Autodesk Fusion 360 part; units mm, degrees
(part 6 of 8)
sketch "Fixed metal roller pin 4 | profile" plane through (0, 0, -17) normal (0, 0, 1) x (1, 0, 0) in component "11:1 twin-disc shoulder | original geometry"
  circle A0 centre (0, 40) radius 1.5
extrude "Fixed metal roller pin 4" add sketch "Fixed metal roller pin 4 | profile" along normal blind 34 separate body makes body 239 in component "11:1 twin-disc shoulder | original geometry"
ref_plane "WorkPlane36" through (0, 0, -6) normal (0, 0, 1) x (1, 0, 0) in component "11:1 twin-disc shoulder | original geometry"
sketch "623ZZ outer race | profile (6)" plane through (0, 0, -6) normal (0, 0, 1) x (1, 0, 0) in component "11:1 twin-disc shoulder | original geometry"
  circle A0 centre (0, 40) radius 5
  circle A1 centre (0, 40) radius 4
extrude "623ZZ outer race (6)" add sketch "623ZZ outer race | profile (6)" along normal blind 4 separate body makes body 240 in component "11:1 twin-disc shoulder | original geometry"
ref_plane "WorkPlane37" through (0, 0, -6) normal (0, 0, 1) x (1, 0, 0) in component "11:1 twin-disc shoulder | original geometry"
sketch "623ZZ inner race | profile (6)" plane through (0, 0, -6) normal (0, 0, 1) x (1, 0, 0) in component "11:1 twin-disc shoulder | original geometry"
  circle A0 centre (0, 40) radius 2.5
  circle A1 centre (0, 40) radius 1.5
extrude "623ZZ inner race (6)" add sketch "623ZZ inner race | profile (6)" along normal blind 4 separate body makes body 241 in component "11:1 twin-disc shoulder | original geometry"
ref_plane "WorkPlane38" through (0, 0, -5.85) normal (0, 0, 1) x (1, 0, 0) in component "11:1 twin-disc shoulder | original geometry"
sketch "623ZZ shield | profile (6)" plane through (0, 0, -5.85) normal (0, 0, 1) x (1, 0, 0) in component "11:1 twin-disc shoulder | original geometry"
  circle A0 centre (0, 40) radius 4
  circle A1 centre (0, 40) radius 2.5
extrude "623ZZ shield (6)" add sketch "623ZZ shield | profile (6)" along normal blind 3.7 separate body makes body 242 in component "11:1 twin-disc shoulder | original geometry"
ref_plane "WorkPlane39" through (0, 0, 2) normal (0, 0, 1) x (1, 0, 0) in component "11:1 twin-disc shoulder | original geometry"
sketch "623ZZ outer race | profile (7)" plane through (0, 0, 2) normal (0, 0, 1) x (1, 0, 0) in component "11:1 twin-disc shoulder | original geometry"
  circle A0 centre (0, 40) radius 5
  circle A1 centre (0, 40) radius 4
extrude "623ZZ outer race (7)" add sketch "623ZZ outer race | profile (7)" along normal blind 4 separate body makes body 243 in component "11:1 twin-disc shoulder | original geometry"
ref_plane "WorkPlane40" through (0, 0, 2) normal (0, 0, 1) x (1, 0, 0) in component "11:1 twin-disc shoulder | original geometry"
sketch "623ZZ inner race | profile (7)" plane through (0, 0, 2) normal (0, 0, 1) x (1, 0, 0) in component "11:1 twin-disc shoulder | original geometry"
  circle A0 centre (0, 40) radius 2.5
  circle A1 centre (0, 40) radius 1.5
extrude "623ZZ inner race (7)" add sketch "623ZZ inner race | profile (7)" along normal blind 4 separate body makes body 244 in component "11:1 twin-disc shoulder | original geometry"
ref_plane "WorkPlane41" through (0, 0, 2.15) normal (0, 0, 1) x (1, 0, 0) in component "11:1 twin-disc shoulder | original geometry"
sketch "623ZZ shield | profile (7)" plane through (0, 0, 2.15) normal (0, 0, 1) x (1, 0, 0) in component "11:1 twin-disc shoulder | original geometry"
  circle A0 centre (0, 40) radius 4
  circle A1 centre (0, 40) radius 2.5
extrude "623ZZ shield (7)" add sketch "623ZZ shield | profile (7)" along normal blind 3.7 separate body makes body 245 in component "11:1 twin-disc shoulder | original geometry"
ref_plane "WorkPlane42" through (0, 0, -17) normal (0, 0, 1) x (1, 0, 0) in component "11:1 twin-disc shoulder | original geometry"
sketch "Fixed metal roller pin 5 | profile" plane through (0, 0, -17) normal (0, 0, 1) x (1, 0, 0) in component "11:1 twin-disc shoulder | original geometry"
  circle A0 centre (-20, 34.641) radius 1.5
extrude "Fixed metal roller pin 5" add sketch "Fixed metal roller pin 5 | profile" along normal blind 34 separate body makes body 246 in component "11:1 twin-disc shoulder | original geometry"
ref_plane "WorkPlane43" through (0, 0, -6) normal (0, 0, 1) x (1, 0, 0) in component "11:1 twin-disc shoulder | original geometry"
sketch "623ZZ outer race | profile (8)" plane through (0, 0, -6) normal (0, 0, 1) x (1, 0, 0) in component "11:1 twin-disc shoulder | original geometry"
  circle A0 centre (-20, 34.641) radius 5
  circle A1 centre (-20, 34.641) radius 4
extrude "623ZZ outer race (8)" add sketch "623ZZ outer race | profile (8)" along normal blind 4 separate body makes body 247 in component "11:1 twin-disc shoulder | original geometry"
ref_plane "WorkPlane44" through (0, 0, -6) normal (0, 0, 1) x (1, 0, 0) in component "11:1 twin-disc shoulder | original geometry"
sketch "623ZZ inner race | profile (8)" plane through (0, 0, -6) normal (0, 0, 1) x (1, 0, 0) in component "11:1 twin-disc shoulder | original geometry"
  circle A0 centre (-20, 34.641) radius 2.5
  circle A1 centre (-20, 34.641) radius 1.5
extrude "623ZZ inner race (8)" add sketch "623ZZ inner race | profile (8)" along normal blind 4 separate body makes body 248 in component "11:1 twin-disc shoulder | original geometry"
ref_plane "WorkPlane45" through (0, 0, -5.85) normal (0, 0, 1) x (1, 0, 0) in component "11:1 twin-disc shoulder | original geometry"
sketch "623ZZ shield | profile (8)" plane through (0, 0, -5.85) normal (0, 0, 1) x (1, 0, 0) in component "11:1 twin-disc shoulder | original geometry"
  circle A0 centre (-20, 34.641) radius 4
  circle A1 centre (-20, 34.641) radius 2.5
extrude "623ZZ shield (8)" add sketch "623ZZ shield | profile (8)" along normal blind 3.7 separate body makes body 249 in component "11:1 twin-disc shoulder | original geometry"
ref_plane "WorkPlane46" through (0, 0, 2) normal (0, 0, 1) x (1, 0, 0) in component "11:1 twin-disc shoulder | original geometry"
sketch "623ZZ outer race | profile (9)" plane through (0, 0, 2) normal (0, 0, 1) x (1, 0, 0) in component "11:1 twin-disc shoulder | original geometry"
  circle A0 centre (-20, 34.641) radius 5
  circle A1 centre (-20, 34.641) radius 4
extrude "623ZZ outer race (9)" add sketch "623ZZ outer race | profile (9)" along normal blind 4 separate body makes body 250 in component "11:1 twin-disc shoulder | original geometry"
ref_plane "WorkPlane47" through (0, 0, 2) normal (0, 0, 1) x (1, 0, 0) in component "11:1 twin-disc shoulder | original geometry"
sketch "623ZZ inner race | profile (9)" plane through (0, 0, 2) normal (0, 0, 1) x (1, 0, 0) in component "11:1 twin-disc shoulder | original geometry"
  circle A0 centre (-20, 34.641) radius 2.5
  circle A1 centre (-20, 34.641) radius 1.5
extrude "623ZZ inner race (9)" add sketch "623ZZ inner race | profile (9)" along normal blind 4 separate body makes body 251 in component "11:1 twin-disc shoulder | original geometry"
ref_plane "WorkPlane48" through (0, 0, 2.15) normal (0, 0, 1) x (1, 0, 0) in component "11:1 twin-disc shoulder | original geometry"
sketch "623ZZ shield | profile (9)" plane through (0, 0, 2.15) normal (0, 0, 1) x (1, 0, 0) in component "11:1 twin-disc shoulder | original geometry"
  circle A0 centre (-20, 34.641) radius 4
  circle A1 centre (-20, 34.641) radius 2.5
extrude "623ZZ shield (9)" add sketch "623ZZ shield | profile (9)" along normal blind 3.7 separate body makes body 252 in component "11:1 twin-disc shoulder | original geometry"
ref_plane "WorkPlane49" through (0, 0, -17) normal (0, 0, 1) x (1, 0, 0) in component "11:1 twin-disc shoulder | original geometry"
sketch "Fixed metal roller pin 6 | profile" plane through (0, 0, -17) normal (0, 0, 1) x (1, 0, 0) in component "11:1 twin-disc shoulder | original geometry"
  circle A0 centre (-34.641, 20) radius 1.5
extrude "Fixed metal roller pin 6" add sketch "Fixed metal roller pin 6 | profile" along normal blind 34 separate body makes body 253 in component "11:1 twin-disc shoulder | original geometry"
ref_plane "WorkPlane50" through (0, 0, -6) normal (0, 0, 1) x (1, 0, 0) in component "11:1 twin-disc shoulder | original geometry"
sketch "623ZZ outer race | profile (10)" plane through (0, 0, -6) normal (0, 0, 1) x (1, 0, 0) in component "11:1 twin-disc shoulder | original geometry"
  circle A0 centre (-34.641, 20) radius 5
  circle A1 centre (-34.641, 20) radius 4
extrude "623ZZ outer race (10)" add sketch "623ZZ outer race | profile (10)" along normal blind 4 separate body makes body 254 in component "11:1 twin-disc shoulder | original geometry"
ref_plane "WorkPlane51" through (0, 0, -6) normal (0, 0, 1) x (1, 0, 0) in component "11:1 twin-disc shoulder | original geometry"
sketch "623ZZ inner race | profile (10)" plane through (0, 0, -6) normal (0, 0, 1) x (1, 0, 0) in component "11:1 twin-disc shoulder | original geometry"
  circle A0 centre (-34.641, 20) radius 2.5
  circle A1 centre (-34.641, 20) radius 1.5
extrude "623ZZ inner race (10)" add sketch "623ZZ inner race | profile (10)" along normal blind 4 separate body makes body 255 in component "11:1 twin-disc shoulder | original geometry"
ref_plane "WorkPlane52" through (0, 0, -5.85) normal (0, 0, 1) x (1, 0, 0) in component "11:1 twin-disc shoulder | original geometry"
sketch "623ZZ shield | profile (10)" plane through (0, 0, -5.85) normal (0, 0, 1) x (1, 0, 0) in component "11:1 twin-disc shoulder | original geometry"
  circle A0 centre (-34.641, 20) radius 4
  circle A1 centre (-34.641, 20) radius 2.5
extrude "623ZZ shield (10)" add sketch "623ZZ shield | profile (10)" along normal blind 3.7 separate body makes body 256 in component "11:1 twin-disc shoulder | original geometry"
ref_plane "WorkPlane53" through (0, 0, 2) normal (0, 0, 1) x (1, 0, 0) in component "11:1 twin-disc shoulder | original geometry"
sketch "623ZZ outer race | profile (11)" plane through (0, 0, 2) normal (0, 0, 1) x (1, 0, 0) in component "11:1 twin-disc shoulder | original geometry"
  circle A0 centre (-34.641, 20) radius 5
  circle A1 centre (-34.641, 20) radius 4
extrude "623ZZ outer race (11)" add sketch "623ZZ outer race | profile (11)" along normal blind 4 separate body makes body 257 in component "11:1 twin-disc shoulder | original geometry"
ref_plane "WorkPlane54" through (0, 0, 2) normal (0, 0, 1) x (1, 0, 0) in component "11:1 twin-disc shoulder | original geometry"
sketch "623ZZ inner race | profile (11)" plane through (0, 0, 2) normal (0, 0, 1) x (1, 0, 0) in component "11:1 twin-disc shoulder | original geometry"
  circle A0 centre (-34.641, 20) radius 2.5
  circle A1 centre (-34.641, 20) radius 1.5
extrude "623ZZ inner race (11)" add sketch "623ZZ inner race | profile (11)" along normal blind 4 separate body makes body 258 in component "11:1 twin-disc shoulder | original geometry"
ref_plane "WorkPlane55" through (0, 0, 2.15) normal (0, 0, 1) x (1, 0, 0) in component "11:1 twin-disc shoulder | original geometry"
sketch "623ZZ shield | profile (11)" plane through (0, 0, 2.15) normal (0, 0, 1) x (1, 0, 0) in component "11:1 twin-disc shoulder | original geometry"
  circle A0 centre (-34.641, 20) radius 4
  circle A1 centre (-34.641, 20) radius 2.5
extrude "623ZZ shield (11)" add sketch "623ZZ shield | profile (11)" along normal blind 3.7 separate body makes body 259 in component "11:1 twin-disc shoulder | original geometry"
ref_plane "WorkPlane56" through (0, 0, -17) normal (0, 0, 1) x (1, 0, 0) in component "11:1 twin-disc shoulder | original geometry"
sketch "Fixed metal roller pin 7 | profile" plane through (0, 0, -17) normal (0, 0, 1) x (1, 0, 0) in component "11:1 twin-disc shoulder | original geometry"
  circle A0 centre (-40, 0) radius 1.5
extrude "Fixed metal roller pin 7" add sketch "Fixed metal roller pin 7 | profile" along normal blind 34 separate body makes body 260 in component "11:1 twin-disc shoulder | original geometry"
ref_plane "WorkPlane57" through (0, 0, -6) normal (0, 0, 1) x (1, 0, 0) in component "11:1 twin-disc shoulder | original geometry"
sketch "623ZZ outer race | profile (12)" plane through (0, 0, -6) normal (0, 0, 1) x (1, 0, 0) in component "11:1 twin-disc shoulder | original geometry"
  circle A0 centre (-40, 0) radius 5
  circle A1 centre (-40, 0) radius 4
extrude "623ZZ outer race (12)" add sketch "623ZZ outer race | profile (12)" along normal blind 4 separate body makes body 261 in component "11:1 twin-disc shoulder | original geometry"
ref_plane "WorkPlane58" through (0, 0, -6) normal (0, 0, 1) x (1, 0, 0) in component "11:1 twin-disc shoulder | original geometry"
sketch "623ZZ inner race | profile (12)" plane through (0, 0, -6) normal (0, 0, 1) x (1, 0, 0) in component "11:1 twin-disc shoulder | original geometry"
  circle A0 centre (-40, 0) radius 2.5
  circle A1 centre (-40, 0) radius 1.5
extrude "623ZZ inner race (12)" add sketch "623ZZ inner race | profile (12)" along normal blind 4 separate body makes body 262 in component "11:1 twin-disc shoulder | original geometry"
ref_plane "WorkPlane59" through (0, 0, -5.85) normal (0, 0, 1) x (1, 0, 0) in component "11:1 twin-disc shoulder | original geometry"
sketch "623ZZ shield | profile (12)" plane through (0, 0, -5.85) normal (0, 0, 1) x (1, 0, 0) in component "11:1 twin-disc shoulder | original geometry"
  circle A0 centre (-40, 0) radius 4
  circle A1 centre (-40, 0) radius 2.5
extrude "623ZZ shield (12)" add sketch "623ZZ shield | profile (12)" along normal blind 3.7 separate body makes body 263 in component "11:1 twin-disc shoulder | original geometry"
ref_plane "WorkPlane60" through (0, 0, 2) normal (0, 0, 1) x (1, 0, 0) in component "11:1 twin-disc shoulder | original geometry"
sketch "623ZZ outer race | profile (13)" plane through (0, 0, 2) normal (0, 0, 1) x (1, 0, 0) in component "11:1 twin-disc shoulder | original geometry"
  circle A0 centre (-40, 0) radius 5
  circle A1 centre (-40, 0) radius 4
extrude "623ZZ outer race (13)" add sketch "623ZZ outer race | profile (13)" along normal blind 4 separate body makes body 264 in component "11:1 twin-disc shoulder | original geometry"
ref_plane "WorkPlane61" through (0, 0, 2) normal (0, 0, 1) x (1, 0, 0) in component "11:1 twin-disc shoulder | original geometry"
sketch "623ZZ inner race | profile (13)" plane through (0, 0, 2) normal (0, 0, 1) x (1, 0, 0) in component "11:1 twin-disc shoulder | original geometry"
  circle A0 centre (-40, 0) radius 2.5
  circle A1 centre (-40, 0) radius 1.5
extrude "623ZZ inner race (13)" add sketch "623ZZ inner race | profile (13)" along normal blind 4 separate body makes body 265 in component "11:1 twin-disc shoulder | original geometry"
ref_plane "WorkPlane62" through (0, 0, 2.15) normal (0, 0, 1) x (1, 0, 0) in component "11:1 twin-disc shoulder | original geometry"
sketch "623ZZ shield | profile (13)" plane through (0, 0, 2.15) normal (0, 0, 1) x (1, 0, 0) in component "11:1 twin-disc shoulder | original geometry"
  circle A0 centre (-40, 0) radius 4
  circle A1 centre (-40, 0) radius 2.5
extrude "623ZZ shield (13)" add sketch "623ZZ shield | profile (13)" along normal blind 3.7 separate body makes body 266 in component "11:1 twin-disc shoulder | original geometry"
ref_plane "WorkPlane63" through (0, 0, -17) normal (0, 0, 1) x (1, 0, 0) in component "11:1 twin-disc shoulder | original geometry"
sketch "Fixed metal roller pin 8 | profile" plane through (0, 0, -17) normal (0, 0, 1) x (1, 0, 0) in component "11:1 twin-disc shoulder | original geometry"
  circle A0 centre (-34.641, -20) radius 1.5
extrude "Fixed metal roller pin 8" add sketch "Fixed metal roller pin 8 | profile" along normal blind 34 separate body makes body 267 in component "11:1 twin-disc shoulder | original geometry"
ref_plane "WorkPlane64" through (0, 0, -6) normal (0, 0, 1) x (1, 0, 0) in component "11:1 twin-disc shoulder | original geometry"
sketch "623ZZ outer race | profile (14)" plane through (0, 0, -6) normal (0, 0, 1) x (1, 0, 0) in component "11:1 twin-disc shoulder | original geometry"
  circle A0 centre (-34.641, -20) radius 5
  circle A1 centre (-34.641, -20) radius 4
extrude "623ZZ outer race (14)" add sketch "623ZZ outer race | profile (14)" along normal blind 4 separate body makes body 268 in component "11:1 twin-disc shoulder | original geometry"
ref_plane "WorkPlane65" through (0, 0, -6) normal (0, 0, 1) x (1, 0, 0) in component "11:1 twin-disc shoulder | original geometry"
sketch "623ZZ inner race | profile (14)" plane through (0, 0, -6) normal (0, 0, 1) x (1, 0, 0) in component "11:1 twin-disc shoulder | original geometry"
  circle A0 centre (-34.641, -20) radius 2.5
  circle A1 centre (-34.641, -20) radius 1.5
extrude "623ZZ inner race (14)" add sketch "623ZZ inner race | profile (14)" along normal blind 4 separate body makes body 269 in component "11:1 twin-disc shoulder | original geometry"
ref_plane "WorkPlane66" through (0, 0, -5.85) normal (0, 0, 1) x (1, 0, 0) in component "11:1 twin-disc shoulder | original geometry"
sketch "623ZZ shield | profile (14)" plane through (0, 0, -5.85) normal (0, 0, 1) x (1, 0, 0) in component "11:1 twin-disc shoulder | original geometry"
  circle A0 centre (-34.641, -20) radius 4
  circle A1 centre (-34.641, -20) radius 2.5
extrude "623ZZ shield (14)" add sketch "623ZZ shield | profile (14)" along normal blind 3.7 separate body makes body 270 in component "11:1 twin-disc shoulder | original geometry"
ref_plane "WorkPlane67" through (0, 0, 2) normal (0, 0, 1) x (1, 0, 0) in component "11:1 twin-disc shoulder | original geometry"
sketch "623ZZ outer race | profile (15)" plane through (0, 0, 2) normal (0, 0, 1) x (1, 0, 0) in component "11:1 twin-disc shoulder | original geometry"
  circle A0 centre (-34.641, -20) radius 5
  circle A1 centre (-34.641, -20) radius 4
extrude "623ZZ outer race (15)" add sketch "623ZZ outer race | profile (15)" along normal blind 4 separate body makes body 271 in component "11:1 twin-disc shoulder | original geometry"
ref_plane "WorkPlane68" through (0, 0, 2) normal (0, 0, 1) x (1, 0, 0) in component "11:1 twin-disc shoulder | original geometry"
sketch "623ZZ inner race | profile (15)" plane through (0, 0, 2) normal (0, 0, 1) x (1, 0, 0) in component "11:1 twin-disc shoulder | original geometry"
  circle A0 centre (-34.641, -20) radius 2.5
  circle A1 centre (-34.641, -20) radius 1.5
extrude "623ZZ inner race (15)" add sketch "623ZZ inner race | profile (15)" along normal blind 4 separate body makes body 272 in component "11:1 twin-disc shoulder | original geometry"
ref_plane "WorkPlane69" through (0, 0, 2.15) normal (0, 0, 1) x (1, 0, 0) in component "11:1 twin-disc shoulder | original geometry"
sketch "623ZZ shield | profile (15)" plane through (0, 0, 2.15) normal (0, 0, 1) x (1, 0, 0) in component "11:1 twin-disc shoulder | original geometry"
  circle A0 centre (-34.641, -20) radius 4
  circle A1 centre (-34.641, -20) radius 2.5
extrude "623ZZ shield (15)" add sketch "623ZZ shield | profile (15)" along normal blind 3.7 separate body makes body 273 in component "11:1 twin-disc shoulder | original geometry"
ref_plane "WorkPlane70" through (0, 0, -17) normal (0, 0, 1) x (1, 0, 0) in component "11:1 twin-disc shoulder | original geometry"
sketch "Fixed metal roller pin 9 | profile" plane through (0, 0, -17) normal (0, 0, 1) x (1, 0, 0) in component "11:1 twin-disc shoulder | original geometry"
  circle A0 centre (-20, -34.641) radius 1.5
extrude "Fixed metal roller pin 9" add sketch "Fixed metal roller pin 9 | profile" along normal blind 34 separate body makes body 274 in component "11:1 twin-disc shoulder | original geometry"
ref_plane "WorkPlane71" through (0, 0, -6) normal (0, 0, 1) x (1, 0, 0) in component "11:1 twin-disc shoulder | original geometry"
sketch "623ZZ outer race | profile (16)" plane through (0, 0, -6) normal (0, 0, 1) x (1, 0, 0) in component "11:1 twin-disc shoulder | original geometry"
  circle A0 centre (-20, -34.641) radius 5
  circle A1 centre (-20, -34.641) radius 4
extrude "623ZZ outer race (16)" add sketch "623ZZ outer race | profile (16)" along normal blind 4 separate body makes body 275 in component "11:1 twin-disc shoulder | original geometry"
ref_plane "WorkPlane72" through (0, 0, -6) normal (0, 0, 1) x (1, 0, 0) in component "11:1 twin-disc shoulder | original geometry"
sketch "623ZZ inner race | profile (16)" plane through (0, 0, -6) normal (0, 0, 1) x (1, 0, 0) in component "11:1 twin-disc shoulder | original geometry"
  circle A0 centre (-20, -34.641) radius 2.5
  circle A1 centre (-20, -34.641) radius 1.5
extrude "623ZZ inner race (16)" add sketch "623ZZ inner race | profile (16)" along normal blind 4 separate body makes body 276 in component "11:1 twin-disc shoulder | original geometry"
ref_plane "WorkPlane73" through (0, 0, -5.85) normal (0, 0, 1) x (1, 0, 0) in component "11:1 twin-disc shoulder | original geometry"
sketch "623ZZ shield | profile (16)" plane through (0, 0, -5.85) normal (0, 0, 1) x (1, 0, 0) in component "11:1 twin-disc shoulder | original geometry"
  circle A0 centre (-20, -34.641) radius 4
  circle A1 centre (-20, -34.641) radius 2.5
extrude "623ZZ shield (16)" add sketch "623ZZ shield | profile (16)" along normal blind 3.7 separate body makes body 277 in component "11:1 twin-disc shoulder | original geometry"
ref_plane "WorkPlane74" through (0, 0, 2) normal (0, 0, 1) x (1, 0, 0) in component "11:1 twin-disc shoulder | original geometry"
sketch "623ZZ outer race | profile (17)" plane through (0, 0, 2) normal (0, 0, 1) x (1, 0, 0) in component "11:1 twin-disc shoulder | original geometry"
  circle A0 centre (-20, -34.641) radius 5
  circle A1 centre (-20, -34.641) radius 4
extrude "623ZZ outer race (17)" add sketch "623ZZ outer race | profile (17)" along normal blind 4 separate body makes body 278 in component "11:1 twin-disc shoulder | original geometry"
ref_plane "WorkPlane75" through (0, 0, 2) normal (0, 0, 1) x (1, 0, 0) in component "11:1 twin-disc shoulder | original geometry"
sketch "623ZZ inner race | profile (17)" plane through (0, 0, 2) normal (0, 0, 1) x (1, 0, 0) in component "11:1 twin-disc shoulder | original geometry"
  circle A0 centre (-20, -34.641) radius 2.5
  circle A1 centre (-20, -34.641) radius 1.5
extrude "623ZZ inner race (17)" add sketch "623ZZ inner race | profile (17)" along normal blind 4 separate body makes body 279 in component "11:1 twin-disc shoulder | original geometry"
ref_plane "WorkPlane76" through (0, 0, 2.15) normal (0, 0, 1) x (1, 0, 0) in component "11:1 twin-disc shoulder | original geometry"
sketch "623ZZ shield | profile (17)" plane through (0, 0, 2.15) normal (0, 0, 1) x (1, 0, 0) in component "11:1 twin-disc shoulder | original geometry"
  circle A0 centre (-20, -34.641) radius 4
  circle A1 centre (-20, -34.641) radius 2.5
extrude "623ZZ shield (17)" add sketch "623ZZ shield | profile (17)" along normal blind 3.7 separate body makes body 280 in component "11:1 twin-disc shoulder | original geometry"
ref_plane "WorkPlane77" through (0, 0, -17) normal (0, 0, 1) x (1, 0, 0) in component "11:1 twin-disc shoulder | original geometry"
sketch "Fixed metal roller pin 10 | profile" plane through (0, 0, -17) normal (0, 0, 1) x (1, 0, 0) in component "11:1 twin-disc shoulder | original geometry"
  circle A0 centre (0, -40) radius 1.5
extrude "Fixed metal roller pin 10" add sketch "Fixed metal roller pin 10 | profile" along normal blind 34 separate body makes body 281 in component "11:1 twin-disc shoulder | original geometry"
ref_plane "WorkPlane78" through (0, 0, -6) normal (0, 0, 1) x (1, 0, 0) in component "11:1 twin-disc shoulder | original geometry"
sketch "623ZZ outer race | profile (18)" plane through (0, 0, -6) normal (0, 0, 1) x (1, 0, 0) in component "11:1 twin-disc shoulder | original geometry"
  circle A0 centre (0, -40) radius 5
  circle A1 centre (0, -40) radius 4
extrude "623ZZ outer race (18)" add sketch "623ZZ outer race | profile (18)" along normal blind 4 separate body makes body 282 in component "11:1 twin-disc shoulder | original geometry"
ref_plane "WorkPlane79" through (0, 0, -6) normal (0, 0, 1) x (1, 0, 0) in component "11:1 twin-disc shoulder | original geometry"
sketch "623ZZ inner race | profile (18)" plane through (0, 0, -6) normal (0, 0, 1) x (1, 0, 0) in component "11:1 twin-disc shoulder | original geometry"
  circle A0 centre (0, -40) radius 2.5
  circle A1 centre (0, -40) radius 1.5
extrude "623ZZ inner race (18)" add sketch "623ZZ inner race | profile (18)" along normal blind 4 separate body makes body 283 in component "11:1 twin-disc shoulder | original geometry"
ref_plane "WorkPlane80" through (0, 0, -5.85) normal (0, 0, 1) x (1, 0, 0) in component "11:1 twin-disc shoulder | original geometry"
sketch "623ZZ shield | profile (18)" plane through (0, 0, -5.85) normal (0, 0, 1) x (1, 0, 0) in component "11:1 twin-disc shoulder | original geometry"
  circle A0 centre (0, -40) radius 4
  circle A1 centre (0, -40) radius 2.5
extrude "623ZZ shield (18)" add sketch "623ZZ shield | profile (18)" along normal blind 3.7 separate body makes body 284 in component "11:1 twin-disc shoulder | original geometry"
ref_plane "WorkPlane81" through (0, 0, 2) normal (0, 0, 1) x (1, 0, 0) in component "11:1 twin-disc shoulder | original geometry"
sketch "623ZZ outer race | profile (19)" plane through (0, 0, 2) normal (0, 0, 1) x (1, 0, 0) in component "11:1 twin-disc shoulder | original geometry"
  circle A0 centre (0, -40) radius 5
  circle A1 centre (0, -40) radius 4
extrude "623ZZ outer race (19)" add sketch "623ZZ outer race | profile (19)" along normal blind 4 separate body makes body 285 in component "11:1 twin-disc shoulder | original geometry"
ref_plane "WorkPlane82" through (0, 0, 2) normal (0, 0, 1) x (1, 0, 0) in component "11:1 twin-disc shoulder | original geometry"
sketch "623ZZ inner race | profile (19)" plane through (0, 0, 2) normal (0, 0, 1) x (1, 0, 0) in component "11:1 twin-disc shoulder | original geometry"
  circle A0 centre (0, -40) radius 2.5
  circle A1 centre (0, -40) radius 1.5
extrude "623ZZ inner race (19)" add sketch "623ZZ inner race | profile (19)" along normal blind 4 separate body makes body 286 in component "11:1 twin-disc shoulder | original geometry"
ref_plane "WorkPlane83" through (0, 0, 2.15) normal (0, 0, 1) x (1, 0, 0) in component "11:1 twin-disc shoulder | original geometry"
sketch "623ZZ shield | profile (19)" plane through (0, 0, 2.15) normal (0, 0, 1) x (1, 0, 0) in component "11:1 twin-disc shoulder | original geometry"
  circle A0 centre (0, -40) radius 4
  circle A1 centre (0, -40) radius 2.5
extrude "623ZZ shield (19)" add sketch "623ZZ shield | profile (19)" along normal blind 3.7 separate body makes body 287 in component "11:1 twin-disc shoulder | original geometry"
ref_plane "WorkPlane84" through (0, 0, -17) normal (0, 0, 1) x (1, 0, 0) in component "11:1 twin-disc shoulder | original geometry"
sketch "Fixed metal roller pin 11 | profile" plane through (0, 0, -17) normal (0, 0, 1) x (1, 0, 0) in component "11:1 twin-disc shoulder | original geometry"
  circle A0 centre (20, -34.641) radius 1.5
extrude "Fixed metal roller pin 11" add sketch "Fixed metal roller pin 11 | profile" along normal blind 34 separate body makes body 288 in component "11:1 twin-disc shoulder | original geometry"
ref_plane "WorkPlane85" through (0, 0, -6) normal (0, 0, 1) x (1, 0, 0) in component "11:1 twin-disc shoulder | original geometry"
sketch "623ZZ outer race | profile (20)" plane through (0, 0, -6) normal (0, 0, 1) x (1, 0, 0) in component "11:1 twin-disc shoulder | original geometry"
  circle A0 centre (20, -34.641) radius 5
  circle A1 centre (20, -34.641) radius 4
extrude "623ZZ outer race (20)" add sketch "623ZZ outer race | profile (20)" along normal blind 4 separate body makes body 289 in component "11:1 twin-disc shoulder | original geometry"
ref_plane "WorkPlane86" through (0, 0, -6) normal (0, 0, 1) x (1, 0, 0) in component "11:1 twin-disc shoulder | original geometry"
sketch "623ZZ inner race | profile (20)" plane through (0, 0, -6) normal (0, 0, 1) x (1, 0, 0) in component "11:1 twin-disc shoulder | original geometry"
  circle A0 centre (20, -34.641) radius 2.5
  circle A1 centre (20, -34.641) radius 1.5
extrude "623ZZ inner race (20)" add sketch "623ZZ inner race | profile (20)" along normal blind 4 separate body makes body 290 in component "11:1 twin-disc shoulder | original geometry"
ref_plane "WorkPlane87" through (0, 0, -5.85) normal (0, 0, 1) x (1, 0, 0) in component "11:1 twin-disc shoulder | original geometry"
sketch "623ZZ shield | profile (20)" plane through (0, 0, -5.85) normal (0, 0, 1) x (1, 0, 0) in component "11:1 twin-disc shoulder | original geometry"
  circle A0 centre (20, -34.641) radius 4
  circle A1 centre (20, -34.641) radius 2.5
extrude "623ZZ shield (20)" add sketch "623ZZ shield | profile (20)" along normal blind 3.7 separate body makes body 291 in component "11:1 twin-disc shoulder | original geometry"
ref_plane "WorkPlane88" through (0, 0, 2) normal (0, 0, 1) x (1, 0, 0) in component "11:1 twin-disc shoulder | original geometry"
sketch "623ZZ outer race | profile (21)" plane through (0, 0, 2) normal (0, 0, 1) x (1, 0, 0) in component "11:1 twin-disc shoulder | original geometry"
  circle A0 centre (20, -34.641) radius 5
  circle A1 centre (20, -34.641) radius 4
extrude "623ZZ outer race (21)" add sketch "623ZZ outer race | profile (21)" along normal blind 4 separate body makes body 292 in component "11:1 twin-disc shoulder | original geometry"
ref_plane "WorkPlane89" through (0, 0, 2) normal (0, 0, 1) x (1, 0, 0) in component "11:1 twin-disc shoulder | original geometry"
sketch "623ZZ inner race | profile (21)" plane through (0, 0, 2) normal (0, 0, 1) x (1, 0, 0) in component "11:1 twin-disc shoulder | original geometry"
  circle A0 centre (20, -34.641) radius 2.5
  circle A1 centre (20, -34.641) radius 1.5
extrude "623ZZ inner race (21)" add sketch "623ZZ inner race | profile (21)" along normal blind 4 separate body makes body 293 in component "11:1 twin-disc shoulder | original geometry"
ref_plane "WorkPlane90" through (0, 0, 2.15) normal (0, 0, 1) x (1, 0, 0) in component "11:1 twin-disc shoulder | original geometry"
sketch "623ZZ shield | profile (21)" plane through (0, 0, 2.15) normal (0, 0, 1) x (1, 0, 0) in component "11:1 twin-disc shoulder | original geometry"
  circle A0 centre (20, -34.641) radius 4
  circle A1 centre (20, -34.641) radius 2.5
extrude "623ZZ shield (21)" add sketch "623ZZ shield | profile (21)" along normal blind 3.7 separate body makes body 294 in component "11:1 twin-disc shoulder | original geometry"
ref_plane "WorkPlane91" through (0, 0, -17) normal (0, 0, 1) x (1, 0, 0) in component "11:1 twin-disc shoulder | original geometry"
sketch "Fixed metal roller pin 12 | profile" plane through (0, 0, -17) normal (0, 0, 1) x (1, 0, 0) in component "11:1 twin-disc shoulder | original geometry"
  circle A0 centre (34.641, -20) radius 1.5
extrude "Fixed metal roller pin 12" add sketch "Fixed metal roller pin 12 | profile" along normal blind 34 separate body makes body 295 in component "11:1 twin-disc shoulder | original geometry"
ref_plane "WorkPlane92" through (0, 0, -6) normal (0, 0, 1) x (1, 0, 0) in component "11:1 twin-disc shoulder | original geometry"
sketch "623ZZ outer race | profile (22)" plane through (0, 0, -6) normal (0, 0, 1) x (1, 0, 0) in component "11:1 twin-disc shoulder | original geometry"
  circle A0 centre (34.641, -20) radius 5
  circle A1 centre (34.641, -20) radius 4
extrude "623ZZ outer race (22)" add sketch "623ZZ outer race | profile (22)" along normal blind 4 separate body makes body 296 in component "11:1 twin-disc shoulder | original geometry"
ref_plane "WorkPlane93" through (0, 0, -6) normal (0, 0, 1) x (1, 0, 0) in component "11:1 twin-disc shoulder | original geometry"
sketch "623ZZ inner race | profile (22)" plane through (0, 0, -6) normal (0, 0, 1) x (1, 0, 0) in component "11:1 twin-disc shoulder | original geometry"
  circle A0 centre (34.641, -20) radius 2.5
  circle A1 centre (34.641, -20) radius 1.5
extrude "623ZZ inner race (22)" add sketch "623ZZ inner race | profile (22)" along normal blind 4 separate body makes body 297 in component "11:1 twin-disc shoulder | original geometry"
ref_plane "WorkPlane94" through (0, 0, -5.85) normal (0, 0, 1) x (1, 0, 0) in component "11:1 twin-disc shoulder | original geometry"
sketch "623ZZ shield | profile (22)" plane through (0, 0, -5.85) normal (0, 0, 1) x (1, 0, 0) in component "11:1 twin-disc shoulder | original geometry"
  circle A0 centre (34.641, -20) radius 4
  circle A1 centre (34.641, -20) radius 2.5
extrude "623ZZ shield (22)" add sketch "623ZZ shield | profile (22)" along normal blind 3.7 separate body makes body 298 in component "11:1 twin-disc shoulder | original geometry"
ref_plane "WorkPlane95" through (0, 0, 2) normal (0, 0, 1) x (1, 0, 0) in component "11:1 twin-disc shoulder | original geometry"
sketch "623ZZ outer race | profile (23)" plane through (0, 0, 2) normal (0, 0, 1) x (1, 0, 0) in component "11:1 twin-disc shoulder | original geometry"
  circle A0 centre (34.641, -20) radius 5
  circle A1 centre (34.641, -20) radius 4
extrude "623ZZ outer race (23)" add sketch "623ZZ outer race | profile (23)" along normal blind 4 separate body makes body 299 in component "11:1 twin-disc shoulder | original geometry"
ref_plane "WorkPlane96" through (0, 0, 2) normal (0, 0, 1) x (1, 0, 0) in component "11:1 twin-disc shoulder | original geometry"
sketch "623ZZ inner race | profile (23)" plane through (0, 0, 2) normal (0, 0, 1) x (1, 0, 0) in component "11:1 twin-disc shoulder | original geometry"
  circle A0 centre (34.641, -20) radius 2.5
  circle A1 centre (34.641, -20) radius 1.5
extrude "623ZZ inner race (23)" add sketch "623ZZ inner race | profile (23)" along normal blind 4 separate body makes body 300 in component "11:1 twin-disc shoulder | original geometry"
ref_plane "WorkPlane97" through (0, 0, 2.15) normal (0, 0, 1) x (1, 0, 0) in component "11:1 twin-disc shoulder | original geometry"
sketch "623ZZ shield | profile (23)" plane through (0, 0, 2.15) normal (0, 0, 1) x (1, 0, 0) in component "11:1 twin-disc shoulder | original geometry"
  circle A0 centre (34.641, -20) radius 4
  circle A1 centre (34.641, -20) radius 2.5
extrude "623ZZ shield (23)" add sketch "623ZZ shield | profile (23)" along normal blind 3.7 separate body makes body 301 in component "11:1 twin-disc shoulder | original geometry"
ref_plane "WorkPlane98" through (0, 0, -11) normal (0, 0, 1) x (1, 0, 0) in component "11:1 twin-disc shoulder | original geometry"
sketch "Output carrier bridge | profile" plane through (0, 0, -11) normal (0, 0, 1) x (1, 0, 0) in component "11:1 twin-disc shoulder | original geometry"
  circle A0 centre (0, 0) radius 27
  circle A1 centre (0, 0) radius 8
extrude "Output carrier bridge" add sketch "Output carrier bridge | profile" along normal blind 3 separate body makes body 302 in component "11:1 twin-disc shoulder | original geometry"
ref_plane "WorkPlane99" through (0, 0, 8) normal (0, 0, 1) x (1, 0, 0) in component "11:1 twin-disc shoulder | original geometry"
sketch "Output carrier bridge | profile (1)" plane through (0, 0, 8) normal (0, 0, 1) x (1, 0, 0) in component "11:1 twin-disc shoulder | original geometry"
  circle A0 centre (0, 0) radius 27
  circle A1 centre (0, 0) radius 8
extrude "Output carrier bridge (1)" add sketch "Output carrier bridge | profile (1)" along normal blind 3 separate body makes body 303 in component "11:1 twin-disc shoulder | original geometry"
ref_plane "WorkPlane100" through (0, 0, -11) normal (0, 0, 1) x (1, 0, 0) in component "11:1 twin-disc shoulder | original geometry"
sketch "Steel output pin 1 | profile" plane through (0, 0, -11) normal (0, 0, 1) x (1, 0, 0) in component "11:1 twin-disc shoulder | original geometry"
  circle A0 centre (22, 0) radius 2
extrude "Steel output pin 1" add sketch "Steel output pin 1 | profile" along normal blind 22 separate body makes body 304 in component "11:1 twin-disc shoulder | original geometry"
ref_plane "WorkPlane101" through (0, 0, -11) normal (0, 0, 1) x (1, 0, 0) in component "11:1 twin-disc shoulder | original geometry"
sketch "Steel output pin 2 | profile" plane through (0, 0, -11) normal (0, 0, 1) x (1, 0, 0) in component "11:1 twin-disc shoulder | original geometry"
  circle A0 centre (11, 19.0526) radius 2
extrude "Steel output pin 2" add sketch "Steel output pin 2 | profile" along normal blind 22 separate body makes body 305 in component "11:1 twin-disc shoulder | original geometry"
ref_plane "WorkPlane102" through (0, 0, -11) normal (0, 0, 1) x (1, 0, 0) in component "11:1 twin-disc shoulder | original geometry"
sketch "Steel output pin 3 | profile" plane through (0, 0, -11) normal (0, 0, 1) x (1, 0, 0) in component "11:1 twin-disc shoulder | original geometry"
  circle A0 centre (-11, 19.0526) radius 2
extrude "Steel output pin 3" add sketch "Steel output pin 3 | profile" along normal blind 22 separate body makes body 306 in component "11:1 twin-disc shoulder | original geometry"
ref_plane "WorkPlane103" through (0, 0, -11) normal (0, 0, 1) x (1, 0, 0) in component "11:1 twin-disc shoulder | original geometry"
sketch "Steel output pin 4 | profile" plane through (0, 0, -11) normal (0, 0, 1) x (1, 0, 0) in component "11:1 twin-disc shoulder | original geometry"
  circle A0 centre (-22, 0) radius 2
extrude "Steel output pin 4" add sketch "Steel output pin 4 | profile" along normal blind 22 separate body makes body 307 in component "11:1 twin-disc shoulder | original geometry"
ref_plane "WorkPlane104" through (0, 0, -11) normal (0, 0, 1) x (1, 0, 0) in component "11:1 twin-disc shoulder | original geometry"
sketch "Steel output pin 5 | profile" plane through (0, 0, -11) normal (0, 0, 1) x (1, 0, 0) in component "11:1 twin-disc shoulder | original geometry"
  circle A0 centre (-11, -19.0526) radius 2
extrude "Steel output pin 5" add sketch "Steel output pin 5 | profile" along normal blind 22 separate body makes body 308 in component "11:1 twin-disc shoulder | original geometry"
ref_plane "WorkPlane105" through (0, 0, -11) normal (0, 0, 1) x (1, 0, 0) in component "11:1 twin-disc shoulder | original geometry"
sketch "Steel output pin 6 | profile" plane through (0, 0, -11) normal (0, 0, 1) x (1, 0, 0) in component "11:1 twin-disc shoulder | original geometry"
  circle A0 centre (11, -19.0526) radius 2
extrude "Steel output pin 6" add sketch "Steel output pin 6 | profile" along normal blind 22 separate body makes body 309 in component "11:1 twin-disc shoulder | original geometry"
ref_plane "WorkPlane106" through (0, 0, -24) normal (0, 0, 1) x (1, 0, 0) in component "11:1 twin-disc shoulder | original geometry"
sketch "Outboard output hub | profile" plane through (0, 0, -24) normal (0, 0, 1) x (1, 0, 0) in component "11:1 twin-disc shoulder | original geometry"
  circle A0 centre (0, 0) radius 15
  circle A1 centre (0, 0) radius 9
extrude "Outboard output hub" add sketch "Outboard output hub | profile" along normal blind 13 separate body makes body 310 in component "11:1 twin-disc shoulder | original geometry"
ref_plane "WorkPlane107" through (0, 0, 11) normal (0, 0, 1) x (1, 0, 0) in component "11:1 twin-disc shoulder | original geometry"
sketch "Outboard output hub | profile (1)" plane through (0, 0, 11) normal (0, 0, 1) x (1, 0, 0) in component "11:1 twin-disc shoulder | original geometry"
  circle A0 centre (0, 0) radius 15
  circle A1 centre (0, 0) radius 9
extrude "Outboard output hub (1)" add sketch "Outboard output hub | profile (1)" along normal blind 13 separate body makes body 311 in component "11:1 twin-disc shoulder | original geometry"
ref_plane "WorkPlane108" through (0, 0, -24) normal (0, 0, 1) x (1, 0, 0) in component "11:1 twin-disc shoulder | original geometry"
sketch "6806 output support outer race | profile" plane through (0, 0, -24) normal (0, 0, 1) x (1, 0, 0) in component "11:1 twin-disc shoulder | original geometry"
  circle A0 centre (0, 0) radius 21
  circle A1 centre (0, 0) radius 20
extrude "6806 output support outer race" add sketch "6806 output support outer race | profile" along normal blind 7 separate body makes body 312 in component "11:1 twin-disc shoulder | original geometry"
ref_plane "WorkPlane109" through (0, 0, -24) normal (0, 0, 1) x (1, 0, 0) in component "11:1 twin-disc shoulder | original geometry"
sketch "6806 output support inner race | profile" plane through (0, 0, -24) normal (0, 0, 1) x (1, 0, 0) in component "11:1 twin-disc shoulder | original geometry"
  circle A0 centre (0, 0) radius 16
  circle A1 centre (0, 0) radius 15
extrude "6806 output support inner race" add sketch "6806 output support inner race | profile" along normal blind 7 separate body makes body 313 in component "11:1 twin-disc shoulder | original geometry"
ref_plane "WorkPlane110" through (0, 0, -23.85) normal (0, 0, 1) x (1, 0, 0) in component "11:1 twin-disc shoulder | original geometry"
sketch "6806 output support shield | profile" plane through (0, 0, -23.85) normal (0, 0, 1) x (1, 0, 0) in component "11:1 twin-disc shoulder | original geometry"
  circle A0 centre (0, 0) radius 20
  circle A1 centre (0, 0) radius 16
extrude "6806 output support shield" add sketch "6806 output support shield | profile" along normal blind 6.7 separate body makes body 314 in component "11:1 twin-disc shoulder | original geometry"
ref_plane "WorkPlane111" through (0, 0, -24) normal (0, 0, 1) x (1, 0, 0) in component "11:1 twin-disc shoulder | original geometry"
sketch "Output bearing collar | profile" plane through (0, 0, -24) normal (0, 0, 1) x (1, 0, 0) in component "11:1 twin-disc shoulder | original geometry"
  circle A0 centre (0, 0) radius 26
  circle A1 centre (0, 0) radius 21.1
extrude "Output bearing collar" add sketch "Output bearing collar | profile" along normal blind 7 separate body makes body 315 in component "11:1 twin-disc shoulder | original geometry"
ref_plane "WorkPlane112" through (0, 0, 17) normal (0, 0, 1) x (1, 0, 0) in component "11:1 twin-disc shoulder | original geometry"
sketch "6806 output support outer race | profile (1)" plane through (0, 0, 17) normal (0, 0, 1) x (1, 0, 0) in component "11:1 twin-disc shoulder | original geometry"
  circle A0 centre (0, 0) radius 21
  circle A1 centre (0, 0) radius 20
extrude "6806 output support outer race (1)" add sketch "6806 output support outer race | profile (1)" along normal blind 7 separate body makes body 316 in component "11:1 twin-disc shoulder | original geometry"
ref_plane "WorkPlane113" through (0, 0, 17) normal (0, 0, 1) x (1, 0, 0) in component "11:1 twin-disc shoulder | original geometry"
sketch "6806 output support inner race | profile (1)" plane through (0, 0, 17) normal (0, 0, 1) x (1, 0, 0) in component "11:1 twin-disc shoulder | original geometry"
  circle A0 centre (0, 0) radius 16
  circle A1 centre (0, 0) radius 15
extrude "6806 output support inner race (1)" add sketch "6806 output support inner race | profile (1)" along normal blind 7 separate body makes body 317 in component "11:1 twin-disc shoulder | original geometry"
ref_plane "WorkPlane114" through (0, 0, 17.15) normal (0, 0, 1) x (1, 0, 0) in component "11:1 twin-disc shoulder | original geometry"
sketch "6806 output support shield | profile (1)" plane through (0, 0, 17.15) normal (0, 0, 1) x (1, 0, 0) in component "11:1 twin-disc shoulder | original geometry"
  circle A0 centre (0, 0) radius 20
  circle A1 centre (0, 0) radius 16
extrude "6806 output support shield (1)" add sketch "6806 output support shield | profile (1)" along normal blind 6.7 separate body makes body 318 in component "11:1 twin-disc shoulder | original geometry"
ref_plane "WorkPlane115" through (0, 0, 17) normal (0, 0, 1) x (1, 0, 0) in component "11:1 twin-disc shoulder | original geometry"
sketch "Output bearing collar | profile (1)" plane through (0, 0, 17) normal (0, 0, 1) x (1, 0, 0) in component "11:1 twin-disc shoulder | original geometry"
  circle A0 centre (0, 0) radius 26
  circle A1 centre (0, 0) radius 21.1
extrude "Output bearing collar (1)" add sketch "Output bearing collar | profile (1)" along normal blind 7 separate body makes body 319 in component "11:1 twin-disc shoulder | original geometry"
ref_plane "WorkPlane116" through (0, 0, -27) normal (0, 0, 1) x (1, 0, 0) in component "11:1 twin-disc shoulder | original geometry"
sketch "Steel input shaft | profile" plane through (0, 0, -27) normal (0, 0, 1) x (1, 0, 0) in component "11:1 twin-disc shoulder | original geometry"
  circle A0 centre (0, 0) radius 3
extrude "Steel input shaft" add sketch "Steel input shaft | profile" along normal blind 82 separate body makes body 320 in component "11:1 twin-disc shoulder | original geometry"
ref_plane "WorkPlane1" through (0, 0, -14) normal (0, 0, 1) x (1, 0, 0) in component "11:1 twin-disc elbow | original geometry"
sketch "Fixed ring | 12 roller stations | profile (2)" plane through (0, 0, -14) normal (0, 0, 1) x (1, 0, 0) in component "11:1 twin-disc elbow | original geometry"
  circle A0 centre (0, 0) radius 38
  circle A1 centre (0, 0) radius 34.4
extrude "Fixed ring | 12 roller stations'" add sketch "Fixed ring | 12 roller stations | profile (2)" along normal blind 28 separate body makes body 321 in component "11:1 twin-disc elbow | original geometry"
ref_plane "WorkPlane2" through (0, 0, -17) normal (0, 0, 1) x (1, 0, 0) in component "11:1 twin-disc elbow | original geometry"
sketch "Rear roller support | profile (2)" plane through (0, 0, -17) normal (0, 0, 1) x (1, 0, 0) in component "11:1 twin-disc elbow | original geometry"
  line L0 (38, 0) -> (37.817, 3.7247)
  line L1 (37.817, 3.7247) -> (37.2698, 7.4134)
  line L2 (37.2698, 7.4134) -> (36.3637, 11.0308)
  line L3 (36.3637, 11.0308) -> (35.1074, 14.542)
  line L4 (35.1074, 14.542) -> (33.513, 17.9131)
  line L5 (33.513, 17.9131) -> (31.5958, 21.1117)
  line L6 (31.5958, 21.1117) -> (29.3744, 24.1069)
  line L7 (29.3744, 24.1069) -> (26.8701, 26.8701)
  line L8 (26.8701, 26.8701) -> (24.1069, 29.3744)
  line L9 (24.1069, 29.3744) -> (21.1117, 31.5958)
  line L10 (21.1117, 31.5958) -> (17.9131, 33.513)
  line L11 (17.9131, 33.513) -> (14.542, 35.1074)
  line L12 (14.542, 35.1074) -> (11.0308, 36.3637)
  line L13 (11.0308, 36.3637) -> (7.4134, 37.2698)
  line L14 (7.4134, 37.2698) -> (3.7247, 37.817)
  line L15 (3.7247, 37.817) -> (0, 38)
  line L16 (0, 38) -> (-3.7247, 37.817)
  line L17 (-3.7247, 37.817) -> (-7.4134, 37.2698)
  line L18 (-7.4134, 37.2698) -> (-11.0308, 36.3637)
  line L19 (-11.0308, 36.3637) -> (-14.542, 35.1074)
  line L20 (-14.542, 35.1074) -> (-17.9131, 33.513)
  line L21 (-17.9131, 33.513) -> (-21.1117, 31.5958)
  line L22 (-21.1117, 31.5958) -> (-24.1069, 29.3744)
  line L23 (-24.1069, 29.3744) -> (-26.8701, 26.8701)
  line L24 (-26.8701, 26.8701) -> (-29.3744, 24.1069)
  line L25 (-29.3744, 24.1069) -> (-31.5958, 21.1117)
  line L26 (-31.5958, 21.1117) -> (-33.513, 17.9131)
  line L27 (-33.513, 17.9131) -> (-35.1074, 14.542)
  line L28 (-35.1074, 14.542) -> (-36.3637, 11.0308)
  line L29 (-36.3637, 11.0308) -> (-37.2698, 7.4134)
  line L30 (-37.2698, 7.4134) -> (-37.817, 3.7247)
  line L31 (-37.817, 3.7247) -> (-38, 0)
  line L32 (-38, 0) -> (-37.817, -3.7247)
  line L33 (-37.817, -3.7247) -> (-37.2698, -7.4134)
  line L34 (-37.2698, -7.4134) -> (-36.3637, -11.0308)
  line L35 (-36.3637, -11.0308) -> (-35.1074, -14.542)
  line L36 (-35.1074, -14.542) -> (-33.513, -17.9131)
  line L37 (-33.513, -17.9131) -> (-31.5958, -21.1117)
  line L38 (-31.5958, -21.1117) -> (-29.3744, -24.1069)
  line L39 (-29.3744, -24.1069) -> (-26.8701, -26.8701)
  line L40 (-26.8701, -26.8701) -> (-24.1069, -29.3744)
  line L41 (-24.1069, -29.3744) -> (-21.1117, -31.5958)
  line L42 (-21.1117, -31.5958) -> (-17.9131, -33.513)
  line L43 (-17.9131, -33.513) -> (-14.542, -35.1074)
  line L44 (-14.542, -35.1074) -> (-11.0308, -36.3637)
  line L45 (-11.0308, -36.3637) -> (-7.4134, -37.2698)
  line L46 (-7.4134, -37.2698) -> (-3.7247, -37.817)
  line L47 (-3.7247, -37.817) -> (0, -38)
  line L48 (0, -38) -> (3.7247, -37.817)
  line L49 (3.7247, -37.817) -> (7.4134, -37.2698)
  line L50 (7.4134, -37.2698) -> (11.0308, -36.3637)
  line L51 (11.0308, -36.3637) -> (14.542, -35.1074)
  line L52 (14.542, -35.1074) -> (17.9131, -33.513)
  line L53 (17.9131, -33.513) -> (21.1117, -31.5958)
  line L54 (21.1117, -31.5958) -> (24.1069, -29.3744)
  line L55 (24.1069, -29.3744) -> (26.8701, -26.8701)
  line L56 (26.8701, -26.8701) -> (29.3744, -24.1069)
  line L57 (29.3744, -24.1069) -> (31.5958, -21.1117)
  line L58 (31.5958, -21.1117) -> (33.513, -17.9131)
  line L59 (33.513, -17.9131) -> (35.1074, -14.542)
  line L60 (35.1074, -14.542) -> (36.3637, -11.0308)
  line L61 (36.3637, -11.0308) -> (37.2698, -7.4134)
  line L62 (37.2698, -7.4134) -> (37.817, -3.7247)
  line L63 (37.817, -3.7247) -> (38, 0)
  circle A0 centre (0, 0) radius 21.1
  circle A1 centre (36, 0) radius 1.6
  circle A2 centre (18, 31.1769) radius 1.6
  circle A3 centre (-18, 31.1769) radius 1.6
  circle A4 centre (-36, 0) radius 1.6
  circle A5 centre (-18, -31.1769) radius 1.6
  circle A6 centre (18, -31.1769) radius 1.6
extrude "Rear roller support'" add sketch "Rear roller support | profile (2)" along normal blind 3 separate body makes body 322 in component "11:1 twin-disc elbow | original geometry"
ref_plane "WorkPlane3" through (0, 0, 14) normal (0, 0, 1) x (1, 0, 0) in component "11:1 twin-disc elbow | original geometry"